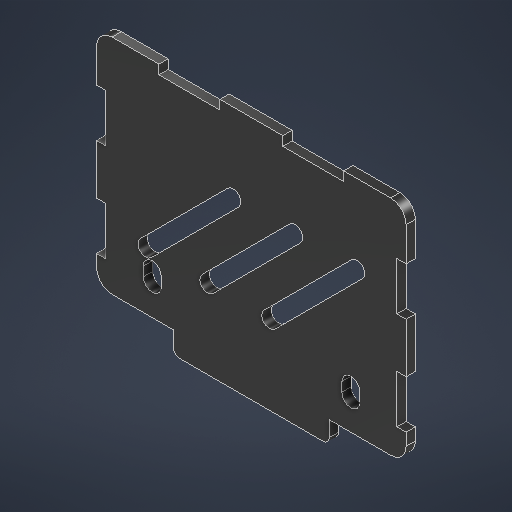
# Autodesk Inventor part: ControlBoxLengthFace
Saved by Autodesk Inventor 2027.1 (Build 311270010, 270A)
## iProperties
Created: 2026-10-13
Part Number: ControlBoxLengthFace
Material: MDF Medium Density Fiberboard
Document SubType Name: Modeling
Designer: SDS Scholar
Density: 0.8 g/cm^3
Appearance: Glossy - Black
Mass: 18.0226 g
Surface Area: 161.468 cm^2
Volume: 22.5282 cm^3
Author: SDS Scholar
Autodesk Inventor part; units mm, degrees
ref_plane "YZ Plane" through (0, 0, 0) normal (1, 0, 0) x (0, 1, 0)
ref_plane "XZ Plane" through (0, 0, 0) normal (0, 1, 0) x (-1, 0, 0)
ref_plane "XY Plane" through (0, 0, 0) normal (0, 0, 1) x (1, 0, 0)
sketch "Sketch1" plane through (0, 0, 0) normal (0, 0, 1) x (1, 0, 0)
  line L0 (-50, 39.5) -> (50, 39.5)
  line L1 (50, 39.5) -> (50, -39.5)
  line L2 (50, -39.5) -> (-50, -39.5)
  line L3 (-50, -39.5) -> (-50, 39.5)
  point P0 (0, 0)
  point P1 (50, 0)
  point P2 (0, 39.5)
  dimension "d0" = 100
  dimension "d1" = 79
  constraints: 8 end point, 2 midpoint, 2 parallel, 1 horizontal, 1 horizontal alignment, 1 perpendicular, 1 vertical alignment
  measures "d0" distance of L0.start L0.end
  measures "d1" distance of L2.end L0.start
extrude "Extrusion1" add sketch "Sketch1" along normal blind 3
sketch "Sketch2" plane through (0, 0, 3) normal (0, 0, 1) x (1, 0, 0)
  line L0 (-50, -39.5) -> (50, -39.5) projected
  line L1 (50, -39.5) -> (50, 39.5) projected
  line L2 (50, 39.5) -> (-50, 39.5) projected
  line L3 (-50, 39.5) -> (-50, -39.5) projected
  line L4 (-47, 36.5) -> (47, 36.5)
  line L5 (47, 36.5) -> (47, -36.5)
  line L6 (47, -36.5) -> (-47, -36.5)
  line L7 (-47, -36.5) -> (-47, 36.5)
  line L8 (-50, 39.5) -> (-29.85, 39.5)
  line L9 (-29.85, 39.5) -> (-29.85, 36.5)
  line L10 (-29.85, 36.5) -> (-50, 36.5)
  line L11 (-50, 36.5) -> (-50, 39.5)
  line L12 (-29.85, 39.5) -> (-10.15, 39.5)
  line L13 (-10.15, 39.5) -> (-10.15, 36.5)
  line L14 (-10.15, 36.5) -> (-29.85, 36.5)
  line L15 (-29.85, 36.5) -> (-29.85, 39.5)
  line L16 (10.15, 39.5) -> (10.15, 36.5)
  line L17 (29.85, 39.5) -> (29.85, 36.5)
  line L18 (-50, 39.5) -> (-47, 39.5)
  line L19 (-47, 39.5) -> (-47, 23.55)
  line L20 (-47, 23.55) -> (-50, 23.55)
  line L21 (-50, 23.55) -> (-50, 39.5)
  line L22 (-50, 23.55) -> (-47, 23.55)
  line L23 (-47, 23.55) -> (-47, 8.05)
  line L24 (-47, 8.05) -> (-50, 8.05)
  line L25 (-50, 8.05) -> (-50, 23.55)
  line L26 (-47, -8.05) -> (-50, -8.05)
  line L27 (-47, -23.55) -> (-50, -23.55)
  line L28 (0, 39.5) -> (0, -39.5) construction
  line L29 (47, 23.55) -> (50, 23.55)
  line L30 (47, 8.05) -> (50, 8.05)
  line L31 (47, -8.05) -> (50, -8.05)
  line L32 (47, -23.55) -> (50, -23.55)
  dimension "d48" = 3
  dimension "d49" = 20.15
  dimension "d50" = 19.7
  dimension "d53" = 40
  dimension "d58" = 15.95
  dimension "d59" = 15.5
  dimension "d62" = 31.6
  constraints: 58 end point, 8 parallel, 8 symmetric about line, 5 horizontal, 4 perpendicular, 4 point on line, 2 midpoint, 1 vertical, 15 other
  measures "d48" distance between parallel lines of L2 L4
  measures "d49" distance of L9.end L10.end
  measures "d50" distance of L13.end L14.end
  measures "d53" distance of L8.end L16.start
  measures "d58" distance of L18.end L19.end
  measures "d59" distance of L22.end L23.end
  measures "d62" distance of L19.end L26.start
extrude "Extrusion2" cut sketch "Sketch2" against normal through all contours L3 L26 L7 L27 | L32 L5 L31 L1 | L3 L20 L7 L24 | L30 L5 L29 L1 | L17 L4 L16 L2 | L9 L2 L13 L4
sketch "Sketch3" plane through (0, 0, 0) normal (0, 0, -1) x (-1, 0, 0)
  line L0 (-34.1421, 14.1421) -> (-5.8579, -14.1421) construction
  line L1 (-35.9099, 12.3744) -> (-7.6256, -15.9099)
  line L2 (-4.0901, -12.3744) -> (-32.3744, 15.9099)
  arc A0 (-32.3744, 15.9099) -> (-35.9099, 12.3744) centre (-34.1421, 14.1421) ccw
  arc A1 (-7.6256, -15.9099) -> (-4.0901, -12.3744) centre (-5.8579, -14.1421) ccw
  line L3 (0, 0) -> (-50, 0)
  line L4 (-14.1421, 14.1421) -> (14.1421, -14.1421) construction
  line L5 (-15.9099, 12.3744) -> (12.3744, -15.9099)
  line L6 (15.9099, -12.3744) -> (-12.3744, 15.9099)
  arc A2 (-12.3744, 15.9099) -> (-15.9099, 12.3744) centre (-14.1421, 14.1421) ccw
  arc A3 (12.3744, -15.9099) -> (15.9099, -12.3744) centre (14.1421, -14.1421) ccw
  line L7 (5.8579, 14.1421) -> (34.1421, -14.1421) construction
  line L8 (4.0901, 12.3744) -> (32.3744, -15.9099)
  line L9 (35.9099, -12.3744) -> (7.6256, 15.9099)
  arc A4 (7.6256, 15.9099) -> (4.0901, 12.3744) centre (5.8579, 14.1421) ccw
  arc A5 (32.3744, -15.9099) -> (35.9099, -12.3744) centre (34.1421, -14.1421) ccw
  line L10 (-50, -39.5) -> (-50, 39.5) projected
  point P0 (-20, 0)
  point P1 (0, 0)
  point P2 (20, 0)
  dimension "d23" = 5
  dimension "d24" = 40
  dimension "d25" = 135
  dimension "d29" = 20
  dimension "d67" = 30
  constraints: 26 end point, 12 point on circle, 6 centre point, 4 tangent, 2 horizontal, 2 midpoint, 1 parallel, 1 point on line, 24 other
  measures "d23" diameter of A1
  measures "d24" distance of L0.start L0.end
  measures "d25" angle of L3 L0
  measures "d29" distance of L1.start L5.start
  measures "d67" distance from line of L10 point (-20, 0)
extrude "Extrusion3" cut sketch "Sketch3" against normal blind 10
sketch "Sketch4" plane through (0, 0, 3) normal (0, 0, 1) x (1, 0, 0)
  line L0 (-35.9099, -12.3744) -> (-7.6256, 15.9099) projected
  arc A0 (-4.0901, 12.3744) -> (-7.6256, 15.9099) centre (-5.8579, 14.1421) ccw projected
  line L1 (-4.0901, 12.3744) -> (-32.3744, -15.9099) projected
  arc A1 (-35.9099, -12.3744) -> (-32.3744, -15.9099) centre (-34.1421, -14.1421) ccw projected
  arc A2 (-15.9099, -12.3744) -> (-12.3744, -15.9099) centre (-14.1421, -14.1421) ccw projected
  line L2 (-15.9099, -12.3744) -> (12.3744, 15.9099) projected
  arc A3 (15.9099, 12.3744) -> (12.3744, 15.9099) centre (14.1421, 14.1421) ccw projected
  line L3 (15.9099, 12.3744) -> (-12.3744, -15.9099) projected
  arc A4 (4.0901, -12.3744) -> (7.6256, -15.9099) centre (5.8579, -14.1421) ccw projected
  line L4 (4.0901, -12.3744) -> (32.3744, 15.9099) projected
  arc A5 (35.9099, 12.3744) -> (32.3744, 15.9099) centre (34.1421, 14.1421) ccw projected
  line L5 (35.9099, 12.3744) -> (7.6256, -15.9099) projected
  line L6 (-50, 39.5) -> (-50, 23.55) projected
  line L7 (-50, -39.5) -> (50, -39.5) projected
  line L8 (50, -39.5) -> (50, -23.55) projected
  line L9 (50, 39.5) -> (29.85, 39.5) projected
  line L10 (-50, -32.5) -> (50, -32.5)
  line L11 (-25.15, -32.5) -> (25.15, -32.5)
  line L12 (25.15, -32.5) -> (25.15, -39.5)
  line L13 (25.15, -39.5) -> (-25.15, -39.5)
  line L14 (-25.15, -39.5) -> (-25.15, -32.5)
  line L15 (47, 23.55) -> (50, 23.55) projected
  line L16 (50, 23.55) -> (50, 39.5) projected
  line L17 (29.85, 39.5) -> (29.85, 36.5) projected
  line L18 (29.85, 36.5) -> (10.15, 36.5) projected
  line L19 (10.15, 36.5) -> (10.15, 39.5) projected
  line L20 (10.15, 39.5) -> (-10.15, 39.5) projected
  line L21 (-10.15, 39.5) -> (-10.15, 36.5) projected
  line L22 (-10.15, 36.5) -> (-29.85, 36.5) projected
  line L23 (-29.85, 36.5) -> (-29.85, 39.5) projected
  line L24 (-29.85, 39.5) -> (-50, 39.5) projected
  line L25 (-50, 23.55) -> (-47, 23.55) projected
  line L26 (-47, 23.55) -> (-47, 8.05) projected
  line L27 (-47, 8.05) -> (-50, 8.05) projected
  line L28 (-50, 8.05) -> (-50, -8.05) projected
  line L29 (-50, -8.05) -> (-47, -8.05) projected
  line L30 (-47, -8.05) -> (-47, -23.55) projected
  line L31 (-47, -23.55) -> (-50, -23.55) projected
  line L32 (-50, -23.55) -> (-50, -39.5) projected
  line L33 (50, -23.55) -> (47, -23.55) projected
  line L34 (47, -23.55) -> (47, -8.05) projected
  line L35 (47, -8.05) -> (50, -8.05) projected
  line L36 (50, -8.05) -> (50, 8.05) projected
  line L37 (50, 8.05) -> (47, 8.05) projected
  line L38 (47, 8.05) -> (47, 23.55) projected
  point P0 (0, 0)
  point P1 (0, -39.5)
  point P2 (0, -39.5)
  dimension "d37" = 7
  dimension "d38" = 50.3
  constraints: 10 end point, 4 point on line, 2 midpoint, 2 parallel, 1 coincident, 1 horizontal, 1 perpendicular
  measures "d37" distance between parallel lines of L7 L10
  measures "d38" distance between parallel lines of L12 L14
extrude "Extrusion4" cut sketch "Sketch4" against normal through all contours L0 A0 L1 A1 | L2 A3 L3 A2 | L4 A5 L5 A4 | L10 L14 L7 L32 | L10 L8 L7 L12
fillet "Fillet1" radius 2 2 edges at (25.15, -39.5, 1.5) (-25.15, -39.5, 1.5)
sketch "Sketch5" plane through (0, 0, 3) normal (0, 0, 1) x (1, 0, 0)
  arc A0 (-25.15, -37.5) -> (-23.15, -39.5) centre (-23.15, -37.5) ccw projected
  line L0 (-23.15, -39.5) -> (23.15, -39.5) projected
  arc A1 (23.15, -39.5) -> (25.15, -37.5) centre (23.15, -37.5) ccw projected
  line L1 (25.15, -37.5) -> (25.15, -32.5) projected
  line L2 (25.15, -32.5) -> (47, -32.5) projected
  line L3 (47, -32.5) -> (47, -24.1) projected
  line L4 (47, -24.1) -> (50, -24.1) projected
  line L5 (50, -24.1) -> (50, -3.8) projected
  line L6 (50, -3.8) -> (47, -3.8) projected
  line L7 (47, -3.8) -> (47, 16.2) projected
  line L8 (47, 16.2) -> (50, 16.2) projected
  line L9 (50, 16.2) -> (50, 36.5) projected
  line L10 (50, 36.5) -> (30.6, 36.5) projected
  line L11 (30.6, 36.5) -> (30.6, 39.5) projected
  line L12 (30.6, 39.5) -> (10.3, 39.5) projected
  line L13 (10.3, 39.5) -> (10.3, 36.5) projected
  line L14 (10.3, 36.5) -> (-9.7, 36.5) projected
  line L15 (-9.7, 36.5) -> (-9.7, 39.5) projected
  line L16 (-9.7, 39.5) -> (-30, 39.5) projected
  line L17 (-30, 39.5) -> (-30, 36.5) projected
  line L18 (-30, 36.5) -> (-50, 36.5) projected
  line L19 (-50, 36.5) -> (-50, 16.2) projected
  line L20 (-50, 16.2) -> (-47, 16.2) projected
  line L21 (-47, 16.2) -> (-47, -3.8) projected
  line L22 (-47, -3.8) -> (-50, -3.8) projected
  line L23 (-50, -3.8) -> (-50, -24.1) projected
  line L24 (-50, -24.1) -> (-47, -24.1) projected
  line L25 (-47, -24.1) -> (-47, -32.5) projected
  line L26 (-47, -32.5) -> (-25.15, -32.5) projected
  line L27 (-25.15, -32.5) -> (-25.15, -37.5) projected
  line L28 (-35.9099, -12.3744) -> (-7.6256, 15.9099) projected
  arc A2 (-4.0901, 12.3744) -> (-7.6256, 15.9099) centre (-5.8579, 14.1421) ccw projected
  line L29 (-4.0901, 12.3744) -> (-32.3744, -15.9099) projected
  arc A3 (-35.9099, -12.3744) -> (-32.3744, -15.9099) centre (-34.1421, -14.1421) ccw projected
  arc A4 (-15.9099, -12.3744) -> (-12.3744, -15.9099) centre (-14.1421, -14.1421) ccw projected
  line L30 (-15.9099, -12.3744) -> (12.3744, 15.9099) projected
  arc A5 (15.9099, 12.3744) -> (12.3744, 15.9099) centre (14.1421, 14.1421) ccw projected
  line L31 (15.9099, 12.3744) -> (-12.3744, -15.9099) projected
  arc A6 (4.0901, -12.3744) -> (7.6256, -15.9099) centre (5.8579, -14.1421) ccw projected
  line L32 (4.0901, -12.3744) -> (32.3744, 15.9099) projected
  arc A7 (35.9099, 12.3744) -> (32.3744, 15.9099) centre (34.1421, 14.1421) ccw projected
  line L33 (35.9099, 12.3744) -> (7.6256, -15.9099) projected
  line L34 (-50, -39.5) -> (23.15, -39.5) projected
  line L35 (0, -39.5) -> (0.3, 36.5) construction
  line L36 (-32, -22.5) -> (-32, -19.5) construction
  line L37 (-29.1, -22.5) -> (-29.1, -19.5)
  line L38 (-34.9, -19.5) -> (-34.9, -22.5)
  arc A8 (-34.9, -22.5) -> (-29.1, -22.5) centre (-32, -22.5) ccw
  arc A9 (-29.1, -19.5) -> (-34.9, -19.5) centre (-32, -19.5) ccw
  line L39 (32.1332, -22.7532) -> (32.1569, -19.7533) construction
  line L40 (29.2333, -22.7303) -> (29.257, -19.7304)
  line L41 (35.0568, -19.7761) -> (35.0331, -22.7761)
  arc A10 (29.2333, -22.7303) -> (35.0331, -22.7761) centre (32.1332, -22.7532) ccw
  arc A11 (35.0568, -19.7761) -> (29.257, -19.7304) centre (32.1569, -19.7533) ccw
  point P0 (0, 0)
  point P1 (-32, -21)
  point P2 (32.1451, -21.2532)
  point P3 (-27.15, -39.5)
  dimension "d42" = 3
  dimension "d43" = 5.8
  dimension "d44" = 10
  dimension "d45" = 15
  constraints: 18 end point, 8 point on circle, 7 symmetric about line, 4 centre point, 4 tangent, 2 midpoint, 1 parallel, 1 point on line, 1 vertical, 2 other
  measures "d42" distance of L36.start L36.end
  measures "d43" diameter of A9
  measures "d44" distance from line of L26 L36.start
  measures "d45" distance between parallel lines of L25 L36
extrude "Extrusion5" cut sketch "Sketch5" against normal blind 10 contours A8 L38 A9 L37 | L40 A11 L41 A10
fillet "Fillet2" radius 5 4 edges at (50, 39.5, 1.5) (50, -32.5, 1.5) (-50, 39.5, 1.5) (-50, -32.5, 1.5)
equation "\"d0\" = ContolBoxLength"
equation "\"GridProcutClearance\" = 5"
equation "\"GridBorderThickness\" = 5"
equation "\"GridBorderFillets\" = 7"
equation "\"GridTotalSize\" = 65"
equation "\"GridRobotClearance\" = 65"
equation "\"AluminiumExtrusionClearance\" = 35"
equation "\"BaseTotalLength\" = 885"
equation "\"WorkspaceLength\" = 515"
equation "\"WorkspaceHeight\" = 183"
equation "\"AxesBaseFillet\" = 15"
equation "\"Zaxis\" = 197"
equation "\"ProductTotalHeight\" = 45"
equation "\"VerticalStroke\" = 105"
equation "\"BackArea\" = 165"
equation "\"CylinderStroke\" = 75"
equation "\"BoxesWidth\" = 125"
equation "\"ContolBoxLength\" = 100"
equation "\"BaseWoodThickness\" = 7"
equation "\"kerf\" = 1.5"
equation "\"Kerf\" = 0.3"
equation "\"RxThickness\" = 1.8"
equation "\"support_2\" = 265"
body "Solid1"
